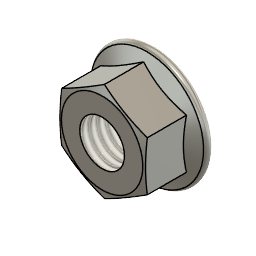
Led_Pyramid (Autodesk Fusion 360 archive; units mm, degrees)
design "Écrou hexagonal DIN 6923 - M8 x 1.25 Acier 6 Standard"
description: Écrou hexagonal DIN 6923 - M8 x 1.25
part number: DIN 6923 - M8x1.25 Acier 6 Standard
Autodesk Fusion 360 part; units mm, degrees
sketch "Sketch1" plane through (0, 0, 0) normal (0, 1, 0) x (1, 0, 0)
  line L0 (0, 0) -> (0, -8)
  line L1 (-4, 0) -> (-7.5075, 0)
  line L2 (-7.5075, 0) -> (-7.5075, -7.643)
  line L3 (-6.175, -8) -> (-4, -8)
  line L4 (-7.5075, -7.643) -> (-6.175, -8)
  line L5 (-4, -8) -> (-4, 0)
  dimension "d149" = 8
  dimension "d150" = 15
  dimension "d151" = 12.35
  dimension "d152" = 8
  dimension "d158" = 15.015
  constraint coincident L0.start L1
  constraint vertical L0
  constraint coincident L0 L0.end
  constraint coincident origin L0
  constraint coincident L0.start origin
  constraint coincident L0.end L3
  constraint horizontal L1
  measures "d149" distance of L1 L3
  measures "d150" angle of L3 L4
revolve "Revolve1" add sketch "Sketch1" angle 360 about axis through (0, 0, 0) along (0, 0, 1)
sketch "Sketch8" plane through (0, 0, 8) normal (0, 0, 1) x (1, 0, 0)
  line L0 (-6.5, -3.7567) -> (-6.5, 3.7567)
  circle A0 centre (0, 0) radius 7.5075
  dimension "d121" = 6.5
  constraint coincident L0.end A0
  constraint coincident L0.start A0
  constraint vertical L0
  measures "d121" distance of A0.centre L0
extrude "Extrude5" cut sketch "Sketch8" against normal blind 8 contours L0 A0 picked at (-6.6626, 0.915)
pattern_circular "C-Pattern2" count 6 over 360 about axis through (0, 0, 1.75) along (0, 0, 1) of "Extrude5"
thread "Thread4" "ISO Metric profile 8.0 M8x1.25 M8x1.25 6H" major diameter 8.17 minor diameter 6.7795 pitch 1.25 angle 60 resizes the face on face at (-3.995, 0.1994, 5.3333)
sketch "Sketch12" plane through (0, 0, 0) normal (1, 0, 0) x (0, 0, -1)
  line L0 (-1.2, 8.5865) -> (-2.3245, 6.175)
  line L1 (-2.3245, 6.175) -> (0, 6.175)
  arc A0 (0, 8.3205) -> (-1.2, 8.5865) centre (-0.6295, 8.3205) ccw
  line L2 (-0.6295, 8.3205) -> (-0.6295, 8.95) construction
  line L3 (0, 0) -> (-8, 0)
  line L4 (0, 8.3205) -> (0, 0)
  line L5 (-0.6295, 8.95) -> (0, 8.95) construction
  dimension "d148" = 25
  dimension "d156" = 0.6295
  dimension "d157" = 17.9
  dimension "d159" = 12.35
  constraint tangent L0 A0
  constraint coincident A0.centre L2.start
  constraint coincident A0 L2.end
  constraint coincident L3.start L4.end
  constraint tangent A0 L4
  constraint coincident L1.end L4
  constraint perpendicular L3 L4
  constraint tangent A0 L5
  constraint coincident L4 L5.end
  measures "d148" angle of L0 L4
  measures "d156" distance of A0.centre L5
revolve "Revolve3" add sketch "Sketch12" angle 360 about axis through (0, 0, 1.75) along (0, 0, 1)
equation "adsk_nheig = 8.00 mm"
equation "adsk_wacor = 15.015 mm"
equation "adsk_nomdia = 8.00 mm"
equation "d89 = -adsk_nheig"
equation "adsk_waflat = 13.00 mm"
equation "adsk_maxdia = 17.90 mm"
equation "adsk_flngheig = 1.20 mm"
equation "d121 = adsk_waflat / 2"
equation "adsk_chamang2 = 15.00 deg"
equation "adsk_flngang = 25.00 deg"
equation "d143 = adsk_nheig"
equation "d148 = adsk_flngang"
equation "d149 = adsk_nheig"
equation "d150 = adsk_chamang2"
equation "d151 = adsk_waflat * 0.95"
equation "d152 = adsk_nomdia"
equation "d156 = adsk_flngheig / ( 1 + cos(adsk_flngang) )"
equation "d157 = adsk_maxdia"
equation "d158 = adsk_wacor"
equation "d159 = adsk_waflat * 0.95"

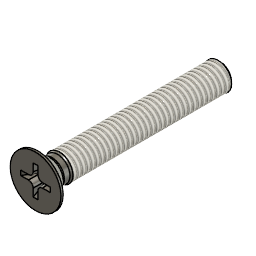
design "Vis à tête fraisée plate SS-ISO 7046-1 - M3 x 20 - H Acier 4.6 Standard"
description: Vis à tête fraisée plate SS-ISO 7046-1 - M3 x 20 - H
part number: SS-ISO 7046-1 - M3 x 20 - H Acier 4.6 Standard
Autodesk Fusion 360 part; units mm, degrees
sketch "Sketch1" plane through (0, 0, 0) normal (0, 1, 0) x (1, 0, 0)
  line L0 (0, -2.9966) -> (-2.75, -2.9966)
  line L1 (-2.75, -2.9966) -> (-2.75, -2.75)
  line L2 (-2.75, -2.75) -> (-1.3466, -1.3466)
  line L3 (-1.5, -0.3466) -> (-1.5, 17.0034)
  line L4 (-1.5, 17.0034) -> (0, 17.0034)
  line L5 (0, 17.0034) -> (0, -2.9966)
  line L6 (-1.3466, -0.6123) -> (-1.3466, -1.3466)
  line L7 (-1.5, -0.3466) -> (-1.3466, -0.6123)
  dimension "d9" = 3
  dimension "d11" = 5.5
  dimension "d71" = 1.65
  dimension "d72" = 2.6933
  dimension "d89" = 17.35
  dimension "d101" = 30
  dimension "d115" = 20
  dimension "d121" = 45
  constraint perpendicular L0 L1
  constraint vertical L3
  constraint perpendicular L3 L4
  constraint perpendicular L0 L5
  constraint collinear origin L0.start L4.end
  constraint horizontal L0
  constraint coincident L2.end L6.end
  constraint coincident L6 L7.end
  constraint coincident L6.start L7.end
  constraint coincident origin L2
  measures "d71" distance of L0 L2.end
  measures "d89" distance of L4 L3.start
  measures "d101" angle of L3 L7
  measures "d115" distance of L0.start L4
  measures "d121" angle of L2 L5
revolve "Revolve1" add sketch "Sketch1" angle 360 about axis through (0, 0, -17.0034) along (0, 0, 1) makes body 1
sketch "Sketch2" plane through (0, 0, 2.9966) normal (0, 0, 1) x (1, 0, 0)
  line L0 (-0.255, 0.255) -> (-1.6, 0.255)
  line L1 (-1.6, 0.255) -> (-1.6, -0.255)
  line L2 (-1.6, -0.255) -> (-0.255, -0.255)
  line L3 (0.255, -1.6) -> (0.255, -0.255)
  line L4 (-0.255, -1.6) -> (0.255, -1.6)
  line L5 (-0.255, -0.255) -> (-0.255, -1.6)
  line L6 (1.6, 0.255) -> (0.255, 0.255)
  line L7 (1.6, -0.255) -> (1.6, 0.255)
  line L8 (0.255, -0.255) -> (1.6, -0.255)
  line L9 (-0.255, 1.6) -> (-0.255, 0.255)
  line L10 (0.255, 1.6) -> (-0.255, 1.6)
  line L11 (0.255, 0.255) -> (0.255, 1.6)
  dimension "d111" = 360
  dimension "d117" = 3.2
  dimension "d122" = 0.51
  constraint horizontal L0
  constraint perpendicular L0 L1
  constraint vertical L0.start L2.end
  constraint coincident L0.start L9.end
  measures "d117" distance of L4.start L10
  measures "d122" distance of L0 L2
extrude "Extrude1" add sketch "Sketch2" against normal blind 2.1 draft -4 separate body makes body 2
draft "Draft1" angle -30 neutral plane through (0, 0, 2.9966) pull (0, 0, 1) 4 faces at (1.5511, 0.0361, 2.2966) (0.0361, 1.5511, 2.2966) (-1.5511, -0.0361, 2.2966) (0.0361, -1.5511, 2.2966) on bodies 2
fillet "Fillet3" radius 0.51 4 edges at (0.1816, 0.1816, 1.9466) (0.1816, -0.1816, 1.9466) (-0.1816, -0.1816, 1.9466) (-0.1816, 0.1816, 1.9466) on bodies 2
combine "Combine1" operation cut target body 1 tool bodies 2
thread "Thread1" "ISO Metric profile 3.0 M3x0.5 M3x0.5 6g" major diameter 2.927 minor diameter 2.3555 pitch 0.5 angle 60 resizes the face on face at (-1.4981, 0.0748, -5.4367) on bodies 1
fillet "Fillet5" radius 0.3 1 edges at (-1.2555, 0.487, 1.3466) on bodies 1
sketch "Sketch6" plane through (0, 0, 0) normal (0, 1, 0) x (1, 0, 0)
  line L0 (-1.1933, 17.0034) -> (-1.53, 17.0034)
  line L1 (-1.53, 17.0034) -> (-1.53, 16.6966)
  line L2 (-1.53, 16.6966) -> (-1.1933, 17.0034)
  line L3 (-1.5, 17.0034) -> (0, 17.0034)
  line L4 (0, 0) -> (0, 17.0034) construction
  dimension "d102" = 1.53
  dimension "d118" = 1.1933
  dimension "d119" = 0.3067
  constraint horizontal L0
  constraint perpendicular L0 L1
  constraint coincident L0.start L3
  constraint coincident L4.start origin
  constraint coincident L3.end L4.end
  measures "d102" distance of L4.start L1
  measures "d118" distance of L0.start L4
  measures "d119" distance of L0 L1.end
revolve "Revolve3" cut sketch "Sketch6" angle 360 about axis through (0, 0, 1.75) along (0, 0, 1) bodies 1
equation "d9 = adsk_nomdia"
equation "d11 = adsk_headdia"
equation "adsk_nomlen = 20.00 mm"
equation "adsk_headh = 1.65 mm"
equation "adsk_headdia = 5.50 mm"
equation "adsk_nomdia = 3.00 mm"
equation "adsk_headang = 90.00 deg"
equation "adsk_phildia = 3.20 mm"
equation "d31 = -adsk_phildepth"
equation "adsk_philwidth = 0.51 mm"
equation "adsk_phildepth = 2.10 mm"
equation "d71 = adsk_headh"
equation "d72 = adsk_shnkdia"
equation "adsk_shnkdia = 2.693275 mm"
equation "d89 = adsk_thrlen"
equation "adsk_thrlen = 17.35 mm"
equation "adsk_pitch1 = 0.50 mm"
equation "adsk_startlen = 0.306725 mm"
equation "adsk_midfillet = adsk_nomdia * 0.1"
equation "d96 = adsk_midfillet"
equation "d99 = ( adsk_shnkdia / 2 ) * tan(90 deg - adsk_headang / 2) + adsk_headh"
equation "d102 = adsk_nomdia * 0.51"
equation "adsk_endpointdia = 2.38655 mm"
equation "d114 = adsk_philwidth"
equation "d115 = adsk_nomlen"
equation "d117 = adsk_phildia"
equation "d118 = adsk_endpointdia / 2"
equation "d119 = adsk_startlen"
equation "d121 = adsk_headang * 0.5"
equation "d122 = adsk_philwidth"

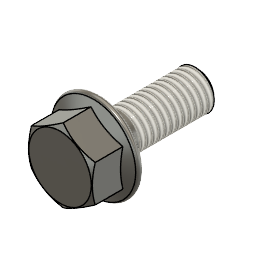
design "Vis à tête hexagonale à embase série lourde ASME B18.2.3.9M - M8 x 1.25 x 20 Acier de classe 2 Standard"
description: Vis à tête hexagonale à embase série lourde ASME B18.2.3.9M - M8 x 1.25 x 20
part number: HHFS ASME B18.2.3.9M - M8 x 1.25 x 20 Acier de classe 2 Standard
Autodesk Fusion 360 part; units mm, degrees
sketch "Sketch1" plane through (0, 0, 0) normal (0, 1, 0) x (1, 0, 0)
  line L0 (-4, 0) -> (-4, 20)
  line L1 (-4, 20) -> (0, 20)
  line L2 (0, 20) -> (0, -8.1)
  line L3 (-4, 0) -> (-7.5075, 0)
  line L4 (-7.5075, 0) -> (-7.5075, -7.4433)
  line L5 (-6.37, -8.1) -> (0, -8.1)
  line L6 (-6.37, -8.1) -> (-7.5075, -7.4433)
  dimension "d9" = 8
  dimension "d111" = 8.1
  dimension "d114" = 15.015
  dimension "d115" = 12.74
  dimension "d159" = 30
  dimension "d165" = 20
  constraint perpendicular L0 L1
  constraint perpendicular L0 L3
  constraint coincident origin L3
  constraint vertical L0
  constraint vertical L2
  constraint coincident L2 L5.end
  constraint coincident L3.end L4.start
  constraint coincident origin L2
  measures "d111" distance of L3 L5
  measures "d159" angle of L5 L6
  measures "d165" distance of origin L1
revolve "Revolve1" add sketch "Sketch1" angle 360 about axis through (0, 0, -20) along (0, 0, 1)
sketch "Sketch8" plane through (0, 0, 8.1) normal (0, 0, 1) x (1, 0, 0)
  line L0 (-6.5, -3.7528) -> (0, -7.5056)
  line L1 (0, -7.5056) -> (6.5, -3.7528)
  line L2 (6.5, -3.7528) -> (6.5, 3.7528)
  line L3 (6.5, 3.7528) -> (0, 7.5056)
  line L4 (0, 7.5056) -> (-6.5, 3.7528)
  line L5 (-6.5, 3.7528) -> (-6.5, -3.7528)
  circle A0 centre (0, 0) radius 7.54
  dimension "d175" = 13
  dimension "d177" = 15.08
  constraint vertical L5
  constraint coincident A0.centre origin
  measures "d175" distance of L2 L5
  measures "d177" diameter of A0
extrude "Extrude5" cut sketch "Sketch8" against normal blind 8.1
sketch "Sketch12" plane through (0, 0, 0) normal (0, 1, 0) x (1, 0, 0)
  line L0 (6.175, 0) -> (8.3181, 0)
  line L1 (8.6063, -1.3) -> (6.175, -2.4337)
  line L2 (6.175, -2.4337) -> (6.175, 0)
  arc A0 (8.6063, -1.3) -> (8.3181, 0) centre (8.3181, -0.6819) ccw
  line L3 (8.3181, -0.6819) -> (9, -0.6819) construction
  line L4 (9, -0.6819) -> (9, 0) construction
  line L5 (0, -1.75) -> (0, -22.5)
  dimension "d161" = 25
  dimension "d172" = 0.6819
  dimension "d173" = 18
  dimension "d174" = 12.35
  constraint tangent L0 A0
  constraint tangent L1 A0
  constraint coincident A0.centre L3.start
  constraint coincident A0 L3.end
  constraint horizontal L3
  constraint tangent A0 L4
  constraint coincident L0 L4.end
  constraint perpendicular L0 L2
  constraint horizontal origin L0.start
  measures "d161" angle of L0 L1
  measures "d172" distance of A0.centre L4
revolve "Revolve3" add sketch "Sketch12" angle 360 about axis through (0, 0, 1.75) along (0, 0, 1)
fillet "Fillet4" radius 0.2667 1 edges at (-3.7293, 1.4465, 0)
thread "Thread2" "ANSI Metric M Profile 8.0 M8x1.25 M8x1.25 6g" major diameter 7.866 minor diameter 6.4455 pitch 1.25 angle 60 resizes the face on face at (-3.995, 0.1994, -6.8444) from (0, 0, -4) to (0, 0, -20)
sketch "Sketch5" plane through (0, 0, 0) normal (0, 1, 0) x (1, 0, 0)
  line L0 (-4.08, 20) -> (-4.08, 19.2332)
  line L1 (-4.08, 19.2332) -> (-3.2332, 20)
  line L2 (0, 20) -> (0, -8.1)
  line L3 (-4.08, 20) -> (0, 20)
  dimension "d166" = 3.2332
  dimension "d167" = 4.08
  dimension "d168" = 0.7668
  constraint coincident L2.start L3.end
  constraint perpendicular L2 L3
  constraint coincident L1.end L3
  constraint perpendicular L0 L3
  measures "d166" distance of L1.end L2
  measures "d167" distance of L0.start L2
  measures "d168" distance of L0.end L3
revolve "Revolve2" cut sketch "Sketch5" angle 360 about axis through (0, 0, -20) along (0, 0, 1)
equation "d9 = adsk_nomdia"
equation "adsk_nomlen = 20.00 mm"
equation "adsk_headh = 8.10 mm"
equation "adsk_nomdia = 8.00 mm"
equation "d89 = -adsk_headh"
equation "adsk_waflat = 13.00 mm"
equation "d111 = adsk_headh"
equation "d114 = adsk_wacor"
equation "d115 = adsk_topdia"
equation "adsk_headdia = 18.00 mm"
equation "adsk_flngheig = 1.30 mm"
equation "adsk_thrlen = 16.00 mm"
equation "d133 = adsk_nomdia / 30"
equation "d144 = min(adsk_thrlen; adsk_nomlen - d133 - 0.01 mm)"
equation "adsk_endpointdia = 6.466375 mm"
equation "adsk_startlen = 0.766813 mm"
equation "adsk_chamang2 = 30.00 deg"
equation "adsk_flngang = 25.00 deg"
equation "d159 = adsk_chamang2"
equation "d161 = adsk_flngang"
equation "adsk_topdia = adsk_waflat * 0.98"
equation "adsk_wacor = 15.015 mm"
equation "d165 = adsk_nomlen"
equation "d166 = adsk_endpointdia / 2"
equation "d167 = adsk_nomdia * 0.51"
equation "d168 = adsk_startlen"
equation "d172 = adsk_flngheig / ( 1 + cos(adsk_flngang) )"
equation "d173 = adsk_headdia"
equation "d174 = adsk_waflat * 0.95"
equation "d175 = adsk_waflat"
equation "d177 = max(adsk_waflat * 1.16; adsk_wacor)"
